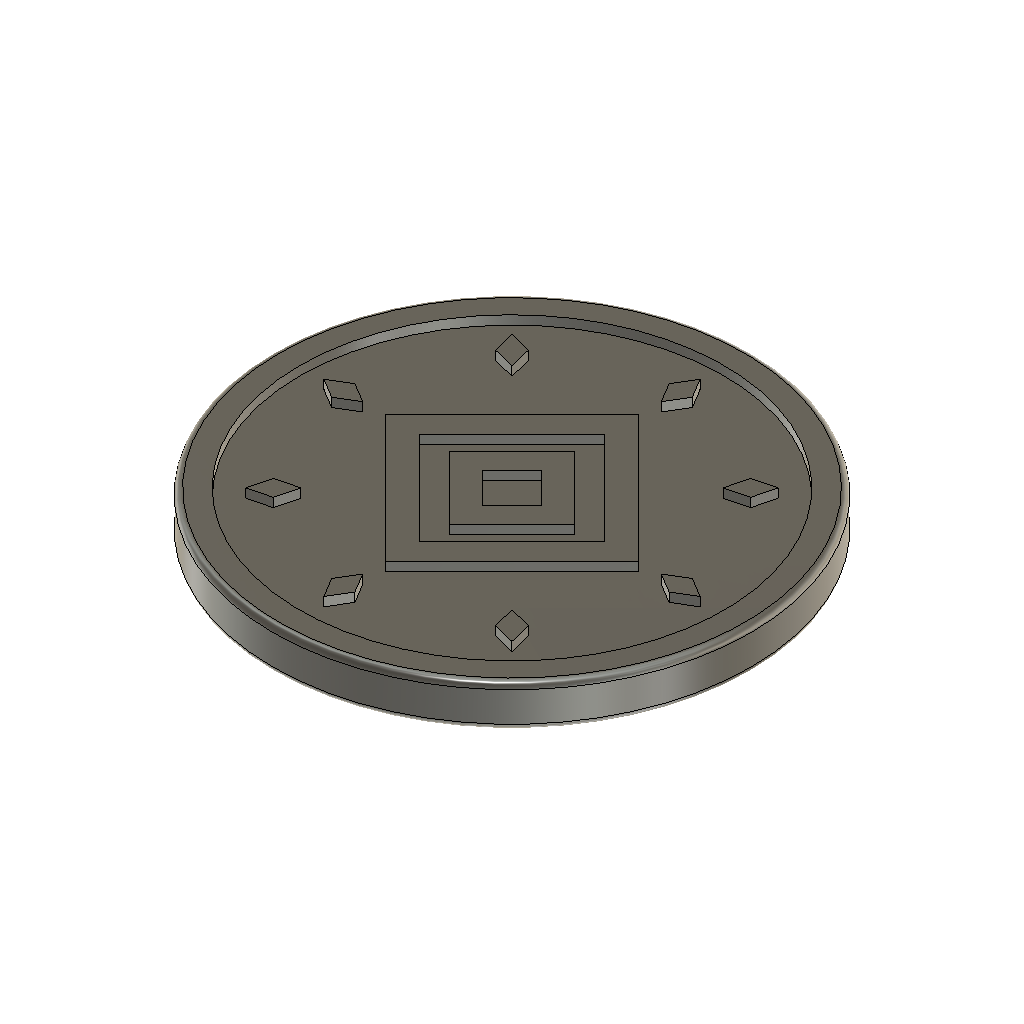
moneda (Autodesk Fusion 360 design; units mm, degrees)
part number: 2026-11-18-21-55-32-735
Autodesk Fusion 360 part; units mm, degrees
sketch "Sketch1" plane through (0, 0, 0) normal (0, 0, 1) x (1, 0, 0)
  circle A0 centre (0, 0) radius 16
extrude "Extrude1" add sketch "Sketch1" along normal blind 2.2
sketch "Sketch2" plane through (0, 0, 2.2) normal (0, 0, 1) x (1, 0, 0)
  circle A0 centre (0, 0) radius 16
  circle A1 centre (0, 0) radius 16
  circle A2 centre (0, 0) radius 14.2
extrude "Extrude2" add sketch "Sketch2" along normal blind 0.6
sketch "Sketch4" plane through (0, 0, 2.2) normal (0, 0, 1) x (1, 0, 0)
  line L0 (12.6, 0) -> (11.3, 0.78)
  line L1 (11.3, 0.78) -> (10, 0)
  line L2 (10, 0) -> (11.3, -0.78)
  line L3 (11.3, -0.78) -> (12.6, 0)
  line L4 (8.9095, 8.9095) -> (7.4388, 8.5418)
  line L5 (7.4388, 8.5418) -> (7.0711, 7.0711)
  line L6 (7.0711, 7.0711) -> (8.5418, 7.4388)
  line L7 (8.5418, 7.4388) -> (8.9095, 8.9095)
  line L8 (0, 12.6) -> (-0.78, 11.3)
  line L9 (-0.78, 11.3) -> (0, 10)
  line L10 (0, 10) -> (0.78, 11.3)
  line L11 (0.78, 11.3) -> (0, 12.6)
  line L12 (-8.9095, 8.9095) -> (-8.5418, 7.4388)
  line L13 (-8.5418, 7.4388) -> (-7.0711, 7.0711)
  line L14 (-7.0711, 7.0711) -> (-7.4388, 8.5418)
  line L15 (-7.4388, 8.5418) -> (-8.9095, 8.9095)
  line L16 (-12.6, 0) -> (-11.3, -0.78)
  line L17 (-11.3, -0.78) -> (-10, 0)
  line L18 (-10, 0) -> (-11.3, 0.78)
  line L19 (-11.3, 0.78) -> (-12.6, 0)
  line L20 (-8.9095, -8.9095) -> (-7.4388, -8.5418)
  line L21 (-7.4388, -8.5418) -> (-7.0711, -7.0711)
  line L22 (-7.0711, -7.0711) -> (-8.5418, -7.4388)
  line L23 (-8.5418, -7.4388) -> (-8.9095, -8.9095)
  line L24 (0, -12.6) -> (0.78, -11.3)
  line L25 (0.78, -11.3) -> (0, -10)
  line L26 (0, -10) -> (-0.78, -11.3)
  line L27 (-0.78, -11.3) -> (0, -12.6)
  line L28 (8.9095, -8.9095) -> (8.5418, -7.4388)
  line L29 (8.5418, -7.4388) -> (7.0711, -7.0711)
  line L30 (7.0711, -7.0711) -> (7.4388, -8.5418)
  line L31 (7.4388, -8.5418) -> (8.9095, -8.9095)
  circle A0 centre (0, 0) radius 14.2
extrude "Extrude4" add sketch "Sketch4" along normal blind 0.6 contours L0 L1 L2 L3 | L4 L5 L6 L7 | L8 L9 L10 L11 | L12 L13 L14 L15 | L16 L17 L18 L19 | L20 L21 L22 L23 | L24 L25 L26 L27 | L28 L29 L30 L31
ref_plane "WorkPlane1" through (0, 0, 2.2) normal (0, 0, 1) x (1, 0, 0)
sketch "RomboCentral" plane through (0, 0, 2.2) normal (0, 0, 1) x (1, 0, 0)
  line L0 (0, 8.5) -> (8.5, 0)
  line L1 (8.5, 0) -> (0, -8.5)
  line L2 (0, -8.5) -> (-8.5, 0)
  line L3 (-8.5, 0) -> (0, 8.5)
  line L4 (0, 6.2) -> (6.2, 0)
  line L5 (6.2, 0) -> (0, -6.2)
  line L6 (0, -6.2) -> (-6.2, 0)
  line L7 (-6.2, 0) -> (0, 6.2)
  line L8 (0, 4.2) -> (4.2, 0)
  line L9 (4.2, 0) -> (0, -4.2)
  line L10 (0, -4.2) -> (-4.2, 0)
  line L11 (-4.2, 0) -> (0, 4.2)
  line L12 (0, 2) -> (2, 0)
  line L13 (2, 0) -> (0, -2)
  line L14 (0, -2) -> (-2, 0)
  line L15 (-2, 0) -> (0, 2)
extrude "Extrude6" add sketch "RomboCentral" along normal blind 0.6
fillet "Fillet1" radius 0.4 2 edges at (-14.9172, -5.7858, 2.8) (-14.9172, -5.7858, 0)
equation "radio = 1.60 cm" comment "Radio de la moneda"
equation "grosor = 0.22 cm" comment "Grosor del disco"
equation "relieve = 0.06 cm" comment "Altura del relieve"
equation "d4 = grosor"
equation "d6 = relieve"
equation "d10 = relieve"
equation "d14 = grosor"
equation "d16 = relieve"
named bodies: "Moneda"
